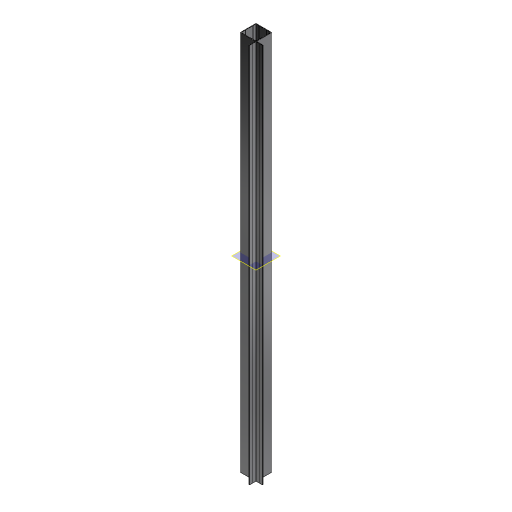
# Autodesk Inventor part: P150 1200mm Y
Saved by Autodesk Inventor 2024.3 (Build 283343000, 343)
## iProperties
Created: 2023-06-01
Part Number: P150 1200mm Y
Material: Aluminium 6061
Document SubType Name: Modellieren
Designer: FarhadPabel
Density: 2.7 g/cm^3
Appearance: Aluminium - flach
Sheet Metal Rule: Stahl 2 mm
Description: Eck-Profil
Mass: 1281.75 g
Surface Area: 5613.93 cm^2
Volume: 474.723 cm^3
Bemerkung: Sägen
Author: FarhadPabel
Autodesk Inventor part; units mm, degrees
ref_plane "YZ Plane" through (0, 0, 0) normal (1, 0, 0) x (0, 1, 0)
ref_plane "XZ Plane" through (0, 0, 0) normal (0, 1, 0) x (-1, 0, 0)
ref_plane "XY Plane" through (0, 0, 0) normal (0, 0, 1) x (1, 0, 0)
sketch "Skizze1" plane through (0, 0, 0) normal (0, 0, 1) x (1, 0, 0)
  line L0 (-25, 25) -> (25, 25)
  line L1 (25, 25) -> (25, -24.7)
  line L2 (24.7, -25) -> (-25, -25)
  line L3 (-25, -25) -> (-25, 25)
  line L4 (-23.3, 23.3) -> (25, -25) construction
  line L5 (25, 25) -> (-25, -25) construction
  line L6 (25, -23) -> (45, -23)
  line L7 (45, -23) -> (45, -24.7)
  line L8 (25, -23.3) -> (25, -23)
  line L9 (23, -25) -> (23.3, -25)
  line L10 (24.7, -45) -> (23, -45)
  line L11 (23, -45) -> (23, -25)
  line L12 (24.7, -35) -> (24.4, -34.7)
  line L13 (24.4, -34.7) -> (24.7, -34.4)
  line L14 (34.4, -24.7) -> (34.7, -24.4)
  line L15 (34.7, -24.4) -> (35, -24.7)
  line L16 (24.7, -25) -> (24.7, -24.7)
  line L17 (24.7, -24.7) -> (25, -24.7)
  line L18 (-14.3, 23.3) -> (-14, 23)
  line L19 (-14, 23) -> (-13.7, 23.3)
  line L20 (-23.3, 14.3) -> (-23, 14)
  line L21 (-23, 14) -> (-23.3, 13.7)
  line L22 (-23.3, -9) -> (-23, -9.3)
  line L23 (-23, -9.3) -> (-23.3, -9.6)
  line L24 (9, 23.3) -> (9.3, 23)
  line L25 (9.3, 23) -> (9.6, 23.3)
  line L26 (23.3, 9.6) -> (23, 9.3)
  line L27 (23, 9.3) -> (23.3, 9)
  line L28 (-9.6, -23.3) -> (-9.3, -23)
  line L29 (-9.3, -23) -> (-9, -23.3)
  line L30 (23.3, -9) -> (23, -9.3)
  line L31 (23, -9.3) -> (23.3, -9.6)
  line L32 (9.3, -23) -> (9.6, -23.3)
  line L33 (9, -23.3) -> (9.3, -23)
  line L34 (24.7, -25) -> (24.7, -34.4)
  line L35 (24.7, -35) -> (24.7, -45)
  line L36 (45, -24.7) -> (35, -24.7)
  line L37 (34.4, -24.7) -> (25, -24.7)
  line L38 (-23.3, -23.3) -> (-9.6, -23.3)
  line L39 (-9, -23.3) -> (9, -23.3)
  line L40 (9.6, -23.3) -> (23.3, -23.3)
  line L41 (23.3, -23.3) -> (23.3, -9.6)
  line L42 (23.3, -9) -> (23.3, 9)
  line L43 (23.3, 9.6) -> (23.3, 23.3)
  line L44 (23.3, 23.3) -> (9.6, 23.3)
  line L45 (9, 23.3) -> (-13.7, 23.3)
  line L46 (-14.3, 23.3) -> (-23.3, 23.3)
  line L47 (-23.3, 23.3) -> (-23.3, 14.3)
  line L48 (-23.3, 13.7) -> (-23.3, -9)
  line L49 (-23.3, -9.6) -> (-23.3, -23.3)
  point P0 (-294.446, -146.0779)
  point P1 (0, 0)
  dimension "d19" = 50
  dimension "d20" = 50
  dimension "d25" = 20
  dimension "d29" = 20
  dimension "d30" = 0.6
  dimension "d31" = 0.3
  dimension "d32" = 10
  dimension "d34" = 0.6
  dimension "d36" = 10
  dimension "d40" = 0.6
  dimension "d42" = 9
  dimension "d43" = 0.6
  dimension "d45" = 9
  dimension "d48" = 23.3
  dimension "d55" = 23.3
  dimension "d60" = 0.6
  dimension "d62" = 0.6
  dimension "d66" = 13.7
  dimension "d69" = 18.6
  dimension "d76" = 18.6
  dimension "d81" = 13.7
  dimension "d82" = 13.7
  dimension "d83" = 135
  dimension "d84" = 0.3
  dimension "d85" = 135
  dimension "d86" = 13.7
  dimension "d87" = 0.3
  dimension "d88" = 0.3
  dimension "d93" = 1.7
  dimension "d94" = 1.7
  dimension "d95" = 2
  dimension "d96" = 2
  dimension "d97" = 135
  dimension "d98" = 135
  dimension "d100" = 1.4
  dimension "d101" = 1.4
  constraints: 100 end point, 26 parallel, 17 perpendicular, 6 point on line, 5 horizontal, 2 vertical, 1 horizontal alignment, 1 midpoint, 20 other
  measures "d19" distance between parallel lines of L1 L3
  measures "d20" distance between parallel lines of L2 L0
  measures "d25" distance from line of L6.end L1
  measures "d29" distance between parallel lines of L10 L9
  measures "d30" distance of L15.end L14.start
  measures "d31" horizontal distance of L14.start L14.end
  measures "d32" distance of L7.end L15.end
  measures "d34" distance of L12.start L13.end
  measures "d36" distance of L10.start L12.start
  measures "d40" distance of L19.end L18.start
  measures "d42" distance of L4.start L18.start
  measures "d43" distance of L21.end L20.start
  measures "d45" distance of L4.start L20.start
  measures "d48" distance of L20.start L22.start
  measures "d55" distance of L18.start L24.start
  measures "d60" distance of L29.end L28.start
  measures "d62" distance of L27.end L26.start
  measures "d66" distance of L26.start L43.end
  measures "d69" distance of L26.start L30.start
  measures "d76" distance of L28.end L32.start
  measures "d81" distance of L28.start L38.start
  measures "d82" distance of L23.end L38.start
  measures "d83" angle of L20 L47
  measures "d84" horizontal distance of L20.start L20.end
  measures "d85" angle of L46 L18
  measures "d86" distance of L43.end L25.end
  measures "d87" distance between parallel lines of L34 L1
  measures "d88" distance between parallel lines of L2 L37
  measures "d93" distance between parallel lines of L11 L35
  measures "d94" distance between parallel lines of L36 L6
  measures "d95" distance between parallel lines of L2 L6
  measures "d96" distance between parallel lines of L1 L11
  measures "d97" angle of L43 L26
  measures "d98" angle of L40 L32
  measures "d100" horizontal distance of L16.end L40.end
  measures "d101" horizontal distance of L16.end L40.end
extrude "Extrusion1" add sketch "Skizze1" along normal blind 1200
fillet "Rundung1" radius 1 2 edges at (-25, -25, 600) (25, 25, 600)
fillet "Rundung2" radius 2 1 edges at (-25, 25, 600)
ref_plane "Arbeitsebene1" through (0, 0, 600) normal (0, 0, -1) x (-1, 0, 0)
equation "\"Biegeradius\" = Stärke"
equation "\"BreiteBiegungsfreistellung\" = Stärke"
equation "\"TiefeBiegungsfreistellung\" = 0.5 * Stärke"
equation "\"GrößeEckenfreistellung\" = 4 * Stärke"
equation "\"MinimalRest\" = 2 * Stärke"
equation "\"Übergangsradius\" = Biegeradius"
equation "\"JacobiRadiusGröße\" = Biegeradius"
equation "\"Abstandsgröße\" = Stärke"
equation "\"Stärke\" = 2"
